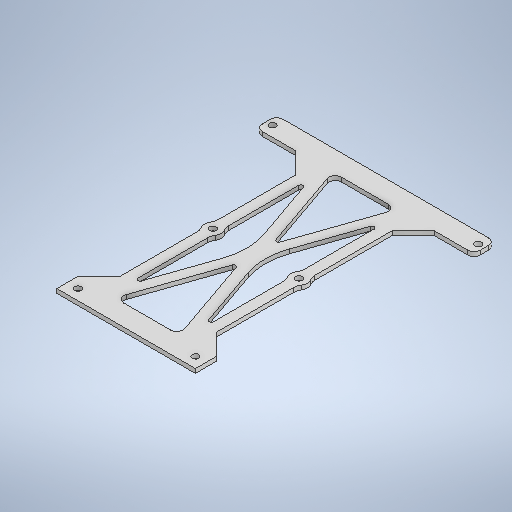
# Autodesk Inventor part: 安装支架
Saved by Autodesk Inventor 2025 (Build 290162000, 162)
## iProperties
Created: 2026-11-18
Part Number: 安装支架
Material: 常规
Document SubType Name: Modeling
Designer: ylh00
Density: 1 g/cm^3
Appearance: 默认
Mass: 13.2652 g
Surface Area: 142.795 cm^2
Volume: 13.2652 cm^3
Author: ylh00
Autodesk Inventor part; units mm, degrees
ref_plane "YZ Plane" through (0, 0, 0) normal (1, 0, 0) x (0, 1, 0)
ref_plane "XZ Plane" through (0, 0, 0) normal (0, 1, 0) x (-1, 0, 0)
ref_plane "XY Plane" through (0, 0, 0) normal (0, 0, 1) x (1, 0, 0)
sketch "草图1" plane through (0, 0, 0) normal (0, 1, 0) x (-1, 0, 0)
  line L0 (0, 0) -> (40, 0)
  line L1 (40, 0) -> (40, -123.75)
  line L2 (40, -123.75) -> (0, -123.75)
  line L3 (0, -123.75) -> (0, 0)
  line L4 (20, -123.75) -> (74, -123.75)
  line L5 (74, -123.75) -> (74, -113.75)
  line L6 (74, -113.75) -> (-34, -113.75)
  line L7 (-34, -113.75) -> (-34, -123.75)
  line L8 (-34, -123.75) -> (74, -123.75)
  line L9 (74, -123.75) -> (74, -113.75)
  circle A0 centre (69, -118.75) radius 1.6
  circle A1 centre (-29, -118.75) radius 1.6
  point P0 (40, -113.75)
  point P1 (0, -113.75)
  dimension "d3" = 10
  dimension "d7" = 3.2
  constraints: 20 end point, 4 parallel, 3 horizontal, 3 perpendicular, 2 centre point, 1 midpoint, 1 point on line
  measures "d3" distance of L5.end L4.end
  measures "d7" diameter of A0
extrude "拉伸1" add sketch "草图1" along normal blind 2
thicken "加厚1" operation cut thickness 2 both sides no extend neighbours no toward (-1, 0, 0) faces at (34, 1.3333, -117.0833)
thicken "加厚2" operation cut thickness 2 both sides no extend neighbours no toward (1, 0, 0) faces at (-74, 1.3333, -120.4167)
fillet "圆角1" radius 3 4 edges at (-72, 1, -123.75) (-72, 1, -113.75) (32, 1, -113.75) (32, 1, -123.75)
sketch "草图2" plane through (0, 2, 0) normal (0, 1, 0) x (1, 0, 0)
  line L0 (-40, 0) -> (0, 0) projected
  line L1 (-20, 0) -> (-53, 0)
  line L2 (-53, 0) -> (-53, 10)
  line L3 (-53, 10) -> (-20, 10)
  line L4 (-20, 10) -> (-20, 0)
  line L5 (-53, 0) -> (13, 0)
  line L6 (13, 0) -> (13, 10)
  line L7 (13, 10) -> (-53, 10)
  line L8 (-53, 10) -> (-53, 0)
  line L9 (-53, 0) -> (-48, 0)
  line L10 (-53, 5) -> (-53, 0)
  line L11 (13, 0) -> (8, 0)
  line L12 (8, 5) -> (13, 5)
  line L13 (13, 5) -> (13, 0)
  circle A0 centre (8, 5) radius 1.6
  circle A1 centre (-48, 5) radius 1.6
  dimension "d18" = 33
  dimension "d19" = 10
  dimension "d20" = 66
  dimension "d23" = 5
  dimension "d24" = 5
  dimension "d26" = 3.2
  constraints: 26 end point, 5 parallel, 4 horizontal, 2 centre point, 2 perpendicular, 1 coincident, 1 midpoint, 1 point on line
  measures "d18" distance of L2.end L3.end
  measures "d19" distance of L1.end L2.end
  measures "d20" distance of L7.end L6.end
  measures "d23" distance of L12.start L12.end
  measures "d24" distance of L11.end L12.start
  measures "d26" diameter of A1
extrude "拉伸2" add sketch "草图2" against normal blind 2
sketch "草图3" plane through (0, 2, 0) normal (0, 1, 0) x (1, 0, 0)
  line L0 (0, 10) -> (13, 10) projected
  line L1 (3, 10) -> (-43, 10)
  line L2 (-43, 10) -> (-43, 113.75)
  line L3 (-43, 113.75) -> (3, 113.75)
  line L4 (3, 113.75) -> (3, 10)
  point P0 (0, 0)
  dimension "d29" = 46
  constraints: 8 end point, 2 parallel, 1 horizontal, 1 perpendicular, 1 point on line
  measures "d29" distance of L2.end L3.end
extrude "拉伸3" add sketch "草图3" against normal blind 2
chamfer "倒角2" distance 10 angle 45 4 edges at (3, 1, -10) (-43, 1, -10) (-43, 1, -113.75) (3, 1, -113.75)
sketch "草图4" plane through (0, 2, 0) normal (0, 1, 0) x (1, 0, 0)
  line L0 (-43, 103.75) -> (-43, 20) projected
  line L1 (-43, 61.875) -> (-38, 61.875)
  line L2 (-38, 126.0174) -> (-38, -4.7804)
  line L3 (-53, 0) -> (13, 0) projected
  line L4 (-20, 0) -> (-20, 10)
  line L5 (29, 123.75) -> (-69, 123.75) projected
  line L6 (-20, 123.75) -> (-20, 113.75)
  line L7 (-2, 126.0174) -> (-2, -4.7804)
  line L8 (-38, 10) -> (-2, 10)
  line L9 (-2, 113.75) -> (-38, 113.75)
  line L10 (-38, 10) -> (-2, 113.75)
  line L11 (-4.3619, 9.1805) -> (-40.3619, 112.9305)
  line L12 (-40.3619, 112.9305) -> (-35.6381, 114.5695)
  line L13 (-35.6381, 114.5695) -> (0.3619, 10.8195)
  line L14 (0.3619, 10.8195) -> (-4.3619, 9.1805)
  line L15 (-4.3619, 9.1805) -> (-35.6381, 114.5695) construction
  line L16 (-40.3619, 112.9305) -> (0.3619, 10.8195) construction
  line L17 (-35.6381, 9.1805) -> (0.3619, 112.9305)
  line L18 (0.3619, 112.9305) -> (-4.3619, 114.5695)
  line L19 (-4.3619, 114.5695) -> (-40.3619, 10.8195)
  line L20 (-40.3619, 10.8195) -> (-35.6381, 9.1805)
  line L21 (-35.6381, 9.1805) -> (-4.3619, 114.5695) construction
  line L22 (0.3619, 112.9305) -> (-40.3619, 10.8195) construction
  point P0 (0, 0)
  point P1 (-20, 61.875)
  point P2 (-20, 61.875)
  point P3 (-20, 69.5013)
  point P4 (-4.6462, 113.75)
  point P5 (-35.3538, 113.75)
  point P6 (-2, 106.1237)
  point P7 (-17.3538, 61.875)
  point P8 (-2, 17.6263)
  point P9 (-38, 17.6263)
  point P10 (-22.6462, 61.875)
  point P11 (-38, 106.1237)
  point P12 (-20, 54.2487)
  point P13 (-35.3538, 10)
  point P14 (-4.6462, 10)
  dimension "d35" = 5
  dimension "d36" = 10
  dimension "d37" = 10
  dimension "d38" = 5
  dimension "d39" = 5
  constraints: 40 end point, 9 midpoint, 5 parallel, 4 perpendicular, 4 point on line, 2 symmetric about line, 2 vertical, 1 horizontal
  measures "d35" distance of L1.start L1.end
  measures "d36" distance of L4.start L4.end
  measures "d37" distance of L6.start L6.end
  measures "d38" distance of L11.end L12.end
  measures "d39" distance of L18.end L17.end
extrude "拉伸4" cut sketch "草图4" against normal blind 2 contours L11 L19 L2 | L9 L19 L13 | L7 L13 L17 | L11 L8 L17
fillet "圆角2" radius 30 2 edges at (-17.3538, 1, -61.875) (-22.6462, 1, -61.875)
fillet "圆角3" radius 1 6 edges at (-38, 1, -17.6263) (-2, 1, -17.6263) (-20, 1, -54.2487) (-20, 1, -69.5013) (-2, 1, -106.1237) (-38, 1, -106.1237)
fillet "圆角4" radius 3 4 edges at (-35.3538, 1, -10) (-4.6462, 1, -10) (-4.6462, 1, -113.75) (-35.3538, 1, -113.75)
sketch "草图7" plane through (0, 2, 0) normal (0, 1, 0) x (1, 0, 0)
  arc A0 (-13.9413, 71.7094) -> (-13.9413, 52.0406) centre (14.4009, 61.875) ccw projected
  line L0 (-2, 100.1913) -> (-2, 23.5587) projected
  line L1 (3, 103.75) -> (3, 20) projected
  line L2 (3, 61.875) -> (-2, 61.875)
  line L3 (-31.1373, 113.75) -> (-8.8627, 113.75) projected
  line L4 (-20, 113.75) -> (-20, 108.9109)
  circle A1 centre (0.5, 61.875) radius 4
  circle A2 centre (-40.5, 61.875) radius 4
  point P0 (0, 0)
  dimension "d50" = 8
  constraints: 4 end point, 4 midpoint, 2 centre point, 1 perpendicular, 1 symmetric about line, 1 vertical, 1 other
  measures "d50" diameter of A1
extrude "拉伸6" add sketch "草图7" against normal blind 2
fillet "圆角5" radius 5 8 edges at (3, 1, -58.7525) (3, 1, -64.9975) (-2, 1, -64.9975) (-2, 1, -58.7525) (-38, 1, -64.9975) (-38, 1, -58.7525) (-43, 1, -58.7525) (-43, 1, -64.9975)
sketch "草图8" plane through (0, 2, 0) normal (0, 1, 0) x (1, 0, 0)
  arc A0 (-37.1667, 59.6639) -> (-37.1667, 64.0861) centre (-40.5, 61.875) ccw projected
  circle A1 centre (-40.5, 61.875) radius 1.6
  arc A2 (3.8333, 59.6639) -> (3.8333, 64.0861) centre (0.5, 61.875) ccw projected
  circle A3 centre (0.5, 61.875) radius 1.6
  point P0 (0, 0)
  dimension "d54" = 3.2
  constraints: 2 centre point, 2 coincident
  measures "d54" diameter of A1
extrude "拉伸7" cut sketch "草图8" against normal blind 2
